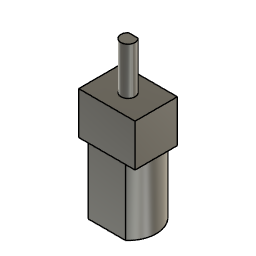
Whole Model (Autodesk Fusion 360 archive; units mm, degrees)
design "N20减速电机 v2"
Autodesk Fusion 360 part; units mm, degrees
(part 1 of 2)
sketch "草图2" plane through (0, 0, 0) normal (0, 0, 1) x (1, 0, 0)
  circle A0 centre (0, 0) radius 1.5
  line L0 (0, 1.12) -> (-0.9978, 1.12)
  line L1 (0, 1.12) -> (0.9978, 1.12)
  dimension "d8" = 3
  dimension "d9" = 1.12
  constraint coincident A0.centre origin
  constraint coincident A0 L0.end
  constraint coincident A0 L1.end
  measures "d8" diameter of A0
  measures "d9" distance of A0.centre L0.start
extrude "拉伸1" add sketch "草图2" along normal blind 10 contours A0 L0 L1 picked at (0.0212, -0.6237) makes body 1
extrude "拉伸2" add sketch "草图2" along normal blind 3 separate body contours A0 L0 L1 picked at (-0.0725, 1.368) makes body 2
sketch "草图4" plane through (0, 0, 0) normal (0, 0, 1) x (1, 0, 0)
  line L0 (-6, 0) -> (-6, -4.5)
  line L1 (-6, -4.5) -> (6, -4.5)
  line L2 (6, -4.5) -> (6, 4.5)
  line L3 (6, 4.5) -> (-6, 4.5)
  line L4 (-6, 4.5) -> (-6, 0)
  dimension "d14" = 6
  dimension "d15" = 4.5
  dimension "d16" = 12
  dimension "d17" = 9
  dimension "d18" = 12
  constraint perpendicular L0 L1
  constraint perpendicular L1 L2
  constraint perpendicular L2 L3
  measures "d14" distance of origin L0.start
  measures "d15" distance of L0.start L0.end
  measures "d16" distance of L0.end L1.end
  measures "d17" distance of L1.end L2.end
  measures "d18" distance of L2.end L3.end
extrude "拉伸3" add sketch "草图4" against normal blind 9 separate body makes body 3
sketch "草图6" plane through (0, 0, -9) normal (0, 0, -1) x (1, 0, 0)
  line L0 (-6, 4.5) -> (-6, -4.5)
  line L1 (-6, -4.5) -> (6, -4.5)
  line L2 (6, -4.5) -> (6, 4.5)
  line L3 (6, 4.5) -> (-6, 4.5)
  line L4 (0, -4.5) -> (0, -4.75)
  line L5 (0, -4.75) -> (3.6657, -4.75)
  line L6 (0, -4.75) -> (-3.6657, -4.75)
  line L7 (0, 4.5) -> (0, 4.75)
  line L8 (0, 4.75) -> (3.6657, 4.75)
  line L9 (0, 4.75) -> (-3.6657, 4.75)
  arc A0 (3.6657, -4.75) -> (3.6657, 4.75) centre (0, 0) ccw
  arc A1 (-3.6657, 4.75) -> (-3.6657, -4.75) centre (0, 0) ccw
  dimension "d21" = 12
  dimension "d22" = 4.75
  dimension "d23" = 4.75
  constraint coincident A0.centre A1.centre
  constraint perpendicular L1 L4
  constraint perpendicular L4 L5
  constraint perpendicular L4 L6
  constraint parallel L4 L7
  constraint perpendicular L7 L8
  constraint coincident L9.end A0
  constraint perpendicular L7 L9
  constraint coincident L1 L4.start
  constraint coincident L3 L7.start
  constraint concentric A0 A1
  measures "d21" diameter of A0
  measures "d22" distance of A0.centre L4.end
  measures "d23" distance of A0.centre L7.end
extrude "拉伸4" add sketch "草图6" along normal blind 14 separate body contours L1 L3 A0 A1 makes body 4
equation "d22 = ( 9.5 / 2 ) * 1 mm"

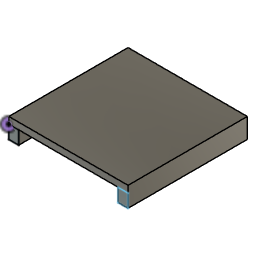
design "電機控製模塊"
Autodesk Fusion 360 part; units mm, degrees
sketch "草图1" plane through (0, 0, 0) normal (0, 0, 1) x (1, 0, 0)
  line L0 (0, 0) -> (18, 0)
  line L1 (18, 0) -> (18, 18)
  line L2 (18, 18) -> (0, 18)
  line L3 (0, 18) -> (0, 0)
  dimension "d1" = 18
  dimension "d2" = 18
  constraint horizontal L0
  constraint vertical L1
  constraint horizontal L2
  constraint vertical L3
  constraint coincident L0.start L3.end
  measures "d1" distance of L0.start L0.end
  measures "d2" distance of L0.start L2.end
extrude "拉伸1" add sketch "草图1" along normal blind 1
sketch "草图2" plane through (0, 0, 0) normal (0, 1, 0) x (1, 0, 0)
  line L0 (0, 0) -> (1.5, 0)
  line L1 (1.5, 0) -> (1.5, 2)
  line L2 (1.5, 2) -> (0, 2)
  line L3 (0, 2) -> (0, 0)
  line L4 (18, 0) -> (16.5, 0)
  line L5 (16.5, 0) -> (16.5, 2)
  line L6 (16.5, 2) -> (18, 2)
  line L7 (18, 2) -> (18, 0)
  dimension "d5" = 1.5
  dimension "d6" = 2
  dimension "d7" = 1.5
  dimension "d8" = 2
  constraint horizontal L0
  constraint vertical L1
  constraint horizontal L2
  constraint vertical L3
  constraint coincident L0.start L3.end
  constraint horizontal L4
  constraint vertical L5
  constraint horizontal L6
  constraint vertical L7
  measures "d5" distance of L0.start L0.end
  measures "d6" distance of L0.start L2.end
  measures "d7" distance of L4.start L4.end
  measures "d8" distance of L4.start L6.end
extrude "拉伸2" add sketch "草图2" along normal blind 18 contours L0 L1 L2 L3
extrude "拉伸3" add sketch "草图2" along normal blind 18 contours L4 L5 L6 L7

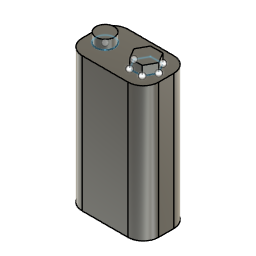
design "9V电池 v1"
Autodesk Fusion 360 part; units mm, degrees
sketch "草图1" plane through (0, 0, 0) normal (0, 0, 1) x (1, 0, 0)
  line L0 (-7.5, 7.5) -> (7.5, 7.5)
  line L1 (12.5, 2.5) -> (12.5, -2.5)
  line L2 (7.5, -7.5) -> (-7.5, -7.5)
  line L3 (-12.5, -2.5) -> (-12.5, 2.5)
  line L4 (-20, 0) -> (35, 0) construction
  line L5 (0, -15) -> (0, 25) construction
  arc A0 (-7.5, 7.5) -> (-12.5, 2.5) centre (-7.5, 2.5) ccw
  arc A1 (12.5, 2.5) -> (7.5, 7.5) centre (7.5, 2.5) ccw
  arc A2 (-12.5, -2.5) -> (-7.5, -7.5) centre (-7.5, -2.5) ccw
  arc A3 (7.5, -7.5) -> (12.5, -2.5) centre (7.5, -2.5) ccw
  point P0 (12.5, 7.5)
  point P1 (12.5, -7.5)
  point P2 (-12.5, -7.5)
  dimension "d1" = 25
  dimension "d2" = 15
  dimension "d3" = 5
  dimension "d4" = 5
  dimension "d5" = 5
  dimension "d6" = 5
  constraint horizontal L0
  constraint vertical L1
  constraint horizontal L2
  constraint vertical L3
  constraint horizontal L4
  constraint vertical L5
  constraint symmetric L1 L3 L5
  constraint symmetric L0 L2 L4
  constraint tangent L3 A0
  constraint tangent L0 A0
  constraint coincident P0 L0
  constraint coincident P0 L1
  constraint tangent L0 A1
  constraint tangent L1 A1
  constraint coincident P2 L3
  constraint coincident P2 L2
  constraint tangent L3 A2
  constraint tangent L2 A2
  constraint coincident P1 L2
  constraint coincident P1 L1
  constraint tangent L2 A3
  constraint tangent L1 A3
  measures "d1" distance of P1 P2
  measures "d2" distance of P0 P1
  measures "d3" radius of A0
  measures "d4" radius of A1
  measures "d5" radius of A2
  measures "d6" radius of A3
extrude "拉伸1" add sketch "草图1" against normal blind 44 makes body 1
sketch "草图3" plane through (0, 0, 0) normal (0, 0, 1) x (1, 0, 0)
  circle A0 centre (-7.5, 0) radius 3
  line L0 (3.9367, 3.4268) -> (2.0007, -0.0735)
  line L1 (4.064, -3.5003) -> (2.0007, -0.0735)
  line L2 (4.064, -3.5003) -> (8.0633, -3.4268)
  line L3 (8.0633, -3.4268) -> (9.9993, 0.0735)
  line L4 (9.9993, 0.0735) -> (7.936, 3.5003)
  line L5 (7.936, 3.5003) -> (3.9367, 3.4268)
  dimension "d9" = 6
  measures "d9" diameter of A0
extrude "拉伸2" add sketch "草图3" along normal blind 3 separate body contours A0 makes body 2
extrude "拉伸3" add sketch "草图3" along normal blind 3 separate body contours L0 L1 L2 L3 L4 L5 makes body 3

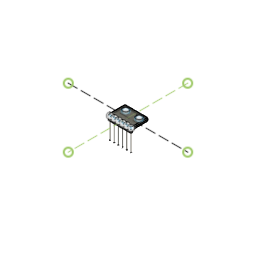
design "BMP280 v2"
Autodesk Fusion 360 part; units mm, degrees
sketch "草图1" plane through (0, 0, 0) normal (0, 0, 1) x (1, 0, 0)
  line L0 (-7.5, 5.5) -> (7.5, 5.5)
  line L1 (7.5, 5.5) -> (7.5, -5.5)
  line L2 (7.5, -5.5) -> (-7.5, -5.5)
  line L3 (-7.5, -5.5) -> (-7.5, 5.5)
  line L4 (0, 40) -> (0, -40) construction
  line L5 (-40, 0) -> (40, 0) construction
  circle A0 centre (-4.5, 3) radius 2
  circle A1 centre (4.5, 3) radius 2
  circle A2 centre (7, -5) radius 0.25
  circle A3 centre (4.2, -5) radius 0.25
  circle A4 centre (1.4, -5) radius 0.25
  circle A5 centre (-1.4, -5) radius 0.25
  circle A6 centre (-4.2, -5) radius 0.25
  circle A7 centre (-7, -5) radius 0.25
  line L6 (-7.5, -5.5) -> (7.5, -5.5)
  line L7 (7.5, -5.5) -> (7.5, -4.5)
  line L8 (7.5, -4.5) -> (-7.5, -4.5)
  line L9 (-7.5, -4.5) -> (-7.5, -5.5)
  dimension "d1" = 15
  dimension "d2" = 11
  dimension "d3" = 4
  dimension "d4" = 4
  dimension "d10" = 0.5
  dimension "d13" = -14
  dimension "d14" = 0
  constraint horizontal L0
  constraint vertical L1
  constraint horizontal L2
  constraint vertical L3
  constraint perpendicular L2 L4
  constraint perpendicular L3 L5
  constraint symmetric L0 L2 L5
  constraint symmetric L1 L3 L4
  constraint horizontal L6
  constraint vertical L7
  constraint horizontal L8
  constraint vertical L9
  constraint coincident L1 L7.end
  measures "d1" distance of L1.end L2.end
  measures "d2" distance of L0.end L1.end
  measures "d3" diameter of A0
  measures "d4" diameter of A1
  measures "d10" diameter of A2
extrude "拉伸1" add sketch "草图1" along normal mid plane 2 makes body 1
extrude "拉伸2" add sketch "草图1" along normal blind 2 separate body contours A7 makes body 2
extrude "拉伸3" add sketch "草图1" against normal blind 14 separate body contours A7 makes body 3
extrude "拉伸4" add sketch "草图1" along normal blind 2 separate body contours A6 makes body 4
extrude "拉伸5" add sketch "草图1" against normal blind 14 separate body contours A6 makes body 5
extrude "拉伸6" add sketch "草图1" along normal blind 2 separate body contours A5 makes body 6
extrude "拉伸7" add sketch "草图1" against normal blind 14 separate body contours A5 makes body 7
extrude "拉伸8" add sketch "草图1" along normal blind 2 separate body contours A4 makes body 8
extrude "拉伸9" add sketch "草图1" against normal blind 14 separate body contours A4 makes body 9
extrude "拉伸10" add sketch "草图1" along normal blind 2 separate body contours A3 makes body 10
extrude "拉伸11" add sketch "草图1" against normal blind 14 separate body contours A3 makes body 11
extrude "拉伸12" add sketch "草图1" along normal blind 2 separate body contours A2 makes body 12
extrude "拉伸13" add sketch "草图1" against normal blind 14 separate body contours A2 makes body 13
sketch "草图2" plane through (0, 0, -1) normal (0, 0, -1) x (1, 0, 0)
  circle A0 centre (4.5, -3) radius 2
  circle A1 centre (-4.5, -3) radius 2
  circle A2 centre (-1.4, 5) radius 0.25
  circle A3 centre (-7, 5) radius 0.25
  circle A4 centre (-4.2, 5) radius 0.25
  circle A5 centre (4.2, 5) radius 0.25
  circle A6 centre (7, 5) radius 0.25
  circle A7 centre (1.4, 5) radius 0.25
  line L0 (7.5, 5.5) -> (-7.5, 5.5)
  line L1 (-7.5, 5.5) -> (-7.5, -5.5)
  line L2 (-7.5, -5.5) -> (7.5, -5.5)
  line L3 (7.5, -5.5) -> (7.5, 5.5)
  line L4 (-7.5, 5.5) -> (7.5, 5.5)
  line L5 (7.5, 5.5) -> (7.5, 4.5)
  line L6 (7.5, 4.5) -> (-7.5, 4.5)
  line L7 (-7.5, 4.5) -> (-7.5, 5.5)
  constraint horizontal L4
  constraint vertical L5
  constraint horizontal L6
  constraint vertical L7
  constraint coincident L3 L5.end
  constraint coincident L0.end L1.start
extrude "拉伸14" add sketch "草图2" along normal blind 1.5 contours L0 L1 L3 L4 L5 L6 L7 bodies 1 3 5 7 9 11 13

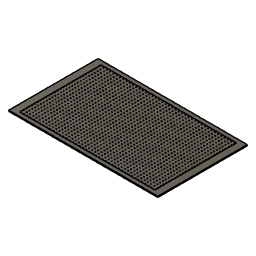
design "9_15万用板 v3"
Autodesk Fusion 360 part; units mm, degrees
sketch "草图1" plane through (0, 0, 0) normal (0, 0, 1) x (1, 0, 0)
  line L0 (-75, 45) -> (-75, -45)
  line L1 (-75, -45) -> (75, -45)
  line L2 (75, -45) -> (75, 45)
  line L3 (75, 45) -> (-75, 45)
  line L4 (0, 70) -> (0, -74.4256) construction
  line L5 (-80, 0) -> (100, 0) construction
  dimension "d1" = 90
  dimension "d2" = 150
  constraint vertical L0
  constraint perpendicular L0 L1
  constraint perpendicular L1 L2
  constraint perpendicular L0 L3
  constraint perpendicular L1 L4
  constraint perpendicular L0 L5
  constraint symmetric L1 L3 L5
  constraint symmetric L0 L2 L4
  measures "d1" distance of L0.start L0.end
  measures "d2" distance of L0.end L1.end
extrude "拉伸1" add sketch "草图1" along normal blind 1 makes body 1
sketch "草图2" plane through (0, 0, 0) normal (0, 0, 1) x (1, 0, 0)
  line L0 (-68, 41) -> (-68, -41)
  line L1 (-68, -41) -> (68, -41)
  line L2 (68, -41) -> (68, 41)
  line L3 (68, 41) -> (-68, 41)
  line L4 (0, 70) -> (0, -74.4256)
  line L5 (-80, 0) -> (100, 0)
  circle A0 centre (-67.5, -40.5) radius 0.5
  circle A1 centre (-64.2073, -40.5) radius 0.5
  circle A2 centre (-60.9146, -40.5) radius 0.5
  circle A3 centre (-57.622, -40.5) radius 0.5
  circle A4 centre (-54.3293, -40.5) radius 0.5
  circle A5 centre (-51.0366, -40.5) radius 0.5
  circle A6 centre (-47.7439, -40.5) radius 0.5
  circle A7 centre (-44.4512, -40.5) radius 0.5
  circle A8 centre (-41.1585, -40.5) radius 0.5
  circle A9 centre (-37.8659, -40.5) radius 0.5
  circle A10 centre (-34.5732, -40.5) radius 0.5
  circle A11 centre (-31.2805, -40.5) radius 0.5
  circle A12 centre (-27.9878, -40.5) radius 0.5
  circle A13 centre (-24.6951, -40.5) radius 0.5
  circle A14 centre (-21.4024, -40.5) radius 0.5
  circle A15 centre (-18.1098, -40.5) radius 0.5
  circle A16 centre (-14.8171, -40.5) radius 0.5
  circle A17 centre (-11.5244, -40.5) radius 0.5
  circle A18 centre (-8.2317, -40.5) radius 0.5
  circle A19 centre (-4.939, -40.5) radius 0.5
  circle A20 centre (-1.6463, -40.5) radius 0.5
  circle A21 centre (1.6463, -40.5) radius 0.5
  circle A22 centre (4.939, -40.5) radius 0.5
  circle A23 centre (8.2317, -40.5) radius 0.5
  circle A24 centre (11.5244, -40.5) radius 0.5
  circle A25 centre (14.8171, -40.5) radius 0.5
  circle A26 centre (18.1098, -40.5) radius 0.5
  circle A27 centre (21.4024, -40.5) radius 0.5
  circle A28 centre (24.6951, -40.5) radius 0.5
  circle A29 centre (27.9878, -40.5) radius 0.5
  circle A30 centre (31.2805, -40.5) radius 0.5
  circle A31 centre (34.5732, -40.5) radius 0.5
  circle A32 centre (37.8659, -40.5) radius 0.5
  circle A33 centre (41.1585, -40.5) radius 0.5
  circle A34 centre (44.4512, -40.5) radius 0.5
  circle A35 centre (47.7439, -40.5) radius 0.5
  circle A36 centre (51.0366, -40.5) radius 0.5
  circle A37 centre (54.3293, -40.5) radius 0.5
  circle A38 centre (57.622, -40.5) radius 0.5
  circle A39 centre (60.9146, -40.5) radius 0.5
  circle A40 centre (64.2073, -40.5) radius 0.5
  circle A41 centre (67.5, -40.5) radius 0.5
  circle A42 centre (-67.5, -37.6429) radius 0.5
  circle A43 centre (-64.2073, -37.6429) radius 0.5
  circle A44 centre (-60.9146, -37.6429) radius 0.5
  circle A45 centre (-57.622, -37.6429) radius 0.5
  circle A46 centre (-54.3293, -37.6429) radius 0.5
  circle A47 centre (-51.0366, -37.6429) radius 0.5
  circle A48 centre (-47.7439, -37.6429) radius 0.5
  circle A49 centre (-44.4512, -37.6429) radius 0.5
  circle A50 centre (-41.1585, -37.6429) radius 0.5
  circle A51 centre (-37.8659, -37.6429) radius 0.5
  circle A52 centre (-34.5732, -37.6429) radius 0.5
  circle A53 centre (-31.2805, -37.6429) radius 0.5
  circle A54 centre (-27.9878, -37.6429) radius 0.5
  circle A55 centre (-24.6951, -37.6429) radius 0.5
  circle A56 centre (-21.4024, -37.6429) radius 0.5
  circle A57 centre (-18.1098, -37.6429) radius 0.5
  circle A58 centre (-14.8171, -37.6429) radius 0.5
  circle A59 centre (-11.5244, -37.6429) radius 0.5
  circle A60 centre (-8.2317, -37.6429) radius 0.5
  circle A61 centre (-4.939, -37.6429) radius 0.5
  circle A62 centre (-1.6463, -37.6429) radius 0.5
  circle A63 centre (1.6463, -37.6429) radius 0.5
  circle A64 centre (4.939, -37.6429) radius 0.5
  circle A65 centre (8.2317, -37.6429) radius 0.5
  circle A66 centre (11.5244, -37.6429) radius 0.5
  circle A67 centre (14.8171, -37.6429) radius 0.5
  circle A68 centre (18.1098, -37.6429) radius 0.5
  circle A69 centre (21.4024, -37.6429) radius 0.5
  circle A70 centre (24.6951, -37.6429) radius 0.5
  circle A71 centre (27.9878, -37.6429) radius 0.5
  circle A72 centre (31.2805, -37.6429) radius 0.5
  circle A73 centre (34.5732, -37.6429) radius 0.5
  circle A74 centre (37.8659, -37.6429) radius 0.5
  circle A75 centre (41.1585, -37.6429) radius 0.5
  circle A76 centre (44.4512, -37.6429) radius 0.5
  circle A77 centre (47.7439, -37.6429) radius 0.5
  circle A78 centre (51.0366, -37.6429) radius 0.5
  circle A79 centre (54.3293, -37.6429) radius 0.5
  circle A80 centre (57.622, -37.6429) radius 0.5
  circle A81 centre (60.9146, -37.6429) radius 0.5
  circle A82 centre (64.2073, -37.6429) radius 0.5
  circle A83 centre (67.5, -37.6429) radius 0.5
  circle A84 centre (-67.5, -34.7857) radius 0.5
  circle A85 centre (-64.2073, -34.7857) radius 0.5
  circle A86 centre (-60.9146, -34.7857) radius 0.5
  circle A87 centre (-57.622, -34.7857) radius 0.5
  circle A88 centre (-54.3293, -34.7857) radius 0.5
  circle A89 centre (-51.0366, -34.7857) radius 0.5
  circle A90 centre (-47.7439, -34.7857) radius 0.5
  circle A91 centre (-44.4512, -34.7857) radius 0.5
  circle A92 centre (-41.1585, -34.7857) radius 0.5
  circle A93 centre (-37.8659, -34.7857) radius 0.5
  circle A94 centre (-34.5732, -34.7857) radius 0.5
  circle A95 centre (-31.2805, -34.7857) radius 0.5
  circle A96 centre (-27.9878, -34.7857) radius 0.5
  circle A97 centre (-24.6951, -34.7857) radius 0.5
  circle A98 centre (-21.4024, -34.7857) radius 0.5
  circle A99 centre (-18.1098, -34.7857) radius 0.5
  circle A100 centre (-14.8171, -34.7857) radius 0.5
  circle A101 centre (-11.5244, -34.7857) radius 0.5
  circle A102 centre (-8.2317, -34.7857) radius 0.5
  circle A103 centre (-4.939, -34.7857) radius 0.5
  circle A104 centre (-1.6463, -34.7857) radius 0.5
  circle A105 centre (1.6463, -34.7857) radius 0.5
  circle A106 centre (4.939, -34.7857) radius 0.5
  circle A107 centre (8.2317, -34.7857) radius 0.5
  circle A108 centre (11.5244, -34.7857) radius 0.5
  circle A109 centre (14.8171, -34.7857) radius 0.5
  circle A110 centre (18.1098, -34.7857) radius 0.5
  circle A111 centre (21.4024, -34.7857) radius 0.5
  circle A112 centre (24.6951, -34.7857) radius 0.5
  circle A113 centre (27.9878, -34.7857) radius 0.5
  circle A114 centre (31.2805, -34.7857) radius 0.5
  circle A115 centre (34.5732, -34.7857) radius 0.5
  circle A116 centre (37.8659, -34.7857) radius 0.5
  circle A117 centre (41.1585, -34.7857) radius 0.5
  circle A118 centre (44.4512, -34.7857) radius 0.5
  circle A119 centre (47.7439, -34.7857) radius 0.5
  circle A120 centre (51.0366, -34.7857) radius 0.5
  circle A121 centre (54.3293, -34.7857) radius 0.5
  circle A122 centre (57.622, -34.7857) radius 0.5
  circle A123 centre (60.9146, -34.7857) radius 0.5
  circle A124 centre (64.2073, -34.7857) radius 0.5
  circle A125 centre (67.5, -34.7857) radius 0.5
  circle A126 centre (-67.5, -31.9286) radius 0.5
  circle A127 centre (-64.2073, -31.9286) radius 0.5
  circle A128 centre (-60.9146, -31.9286) radius 0.5
  circle A129 centre (-57.622, -31.9286) radius 0.5
  circle A130 centre (-54.3293, -31.9286) radius 0.5
  circle A131 centre (-51.0366, -31.9286) radius 0.5
  circle A132 centre (-47.7439, -31.9286) radius 0.5
  circle A133 centre (-44.4512, -31.9286) radius 0.5
  circle A134 centre (-41.1585, -31.9286) radius 0.5
  circle A135 centre (-37.8659, -31.9286) radius 0.5
  circle A136 centre (-34.5732, -31.9286) radius 0.5
  circle A137 centre (-31.2805, -31.9286) radius 0.5
  circle A138 centre (-27.9878, -31.9286) radius 0.5
  circle A139 centre (-24.6951, -31.9286) radius 0.5
  circle A140 centre (-21.4024, -31.9286) radius 0.5
  circle A141 centre (-18.1098, -31.9286) radius 0.5
  circle A142 centre (-14.8171, -31.9286) radius 0.5
  circle A143 centre (-11.5244, -31.9286) radius 0.5
  circle A144 centre (-8.2317, -31.9286) radius 0.5
  circle A145 centre (-4.939, -31.9286) radius 0.5
  circle A146 centre (-1.6463, -31.9286) radius 0.5
  circle A147 centre (1.6463, -31.9286) radius 0.5
  circle A148 centre (4.939, -31.9286) radius 0.5
  circle A149 centre (8.2317, -31.9286) radius 0.5
  circle A150 centre (11.5244, -31.9286) radius 0.5
  circle A151 centre (14.8171, -31.9286) radius 0.5
  circle A152 centre (18.1098, -31.9286) radius 0.5
  circle A153 centre (21.4024, -31.9286) radius 0.5
  circle A154 centre (24.6951, -31.9286) radius 0.5
  circle A155 centre (27.9878, -31.9286) radius 0.5
  circle A156 centre (31.2805, -31.9286) radius 0.5
  circle A157 centre (34.5732, -31.9286) radius 0.5
  circle A158 centre (37.8659, -31.9286) radius 0.5
  circle A159 centre (41.1585, -31.9286) radius 0.5
  circle A160 centre (44.4512, -31.9286) radius 0.5
  circle A161 centre (47.7439, -31.9286) radius 0.5
  circle A162 centre (51.0366, -31.9286) radius 0.5
  circle A163 centre (54.3293, -31.9286) radius 0.5
  circle A164 centre (57.622, -31.9286) radius 0.5
  circle A165 centre (60.9146, -31.9286) radius 0.5
  circle A166 centre (64.2073, -31.9286) radius 0.5
  circle A167 centre (67.5, -31.9286) radius 0.5
  circle A168 centre (-67.5, -29.0714) radius 0.5
  circle A169 centre (-64.2073, -29.0714) radius 0.5
  circle A170 centre (-60.9146, -29.0714) radius 0.5
  circle A171 centre (-57.622, -29.0714) radius 0.5
  circle A172 centre (-54.3293, -29.0714) radius 0.5
  circle A173 centre (-51.0366, -29.0714) radius 0.5
  circle A174 centre (-47.7439, -29.0714) radius 0.5
  circle A175 centre (-44.4512, -29.0714) radius 0.5
  circle A176 centre (-41.1585, -29.0714) radius 0.5
  circle A177 centre (-37.8659, -29.0714) radius 0.5
  circle A178 centre (-34.5732, -29.0714) radius 0.5
  circle A179 centre (-31.2805, -29.0714) radius 0.5
  circle A180 centre (-27.9878, -29.0714) radius 0.5
  circle A181 centre (-24.6951, -29.0714) radius 0.5
  circle A182 centre (-21.4024, -29.0714) radius 0.5
  circle A183 centre (-18.1098, -29.0714) radius 0.5
  circle A184 centre (-14.8171, -29.0714) radius 0.5
  circle A185 centre (-11.5244, -29.0714) radius 0.5
  circle A186 centre (-8.2317, -29.0714) radius 0.5
  circle A187 centre (-4.939, -29.0714) radius 0.5
  circle A188 centre (-1.6463, -29.0714) radius 0.5
  circle A189 centre (1.6463, -29.0714) radius 0.5
  circle A190 centre (4.939, -29.0714) radius 0.5
  circle A191 centre (8.2317, -29.0714) radius 0.5
  circle A192 centre (11.5244, -29.0714) radius 0.5
  circle A193 centre (14.8171, -29.0714) radius 0.5
  circle A194 centre (18.1098, -29.0714) radius 0.5
  circle A195 centre (21.4024, -29.0714) radius 0.5
  circle A196 centre (24.6951, -29.0714) radius 0.5
  circle A197 centre (27.9878, -29.0714) radius 0.5
  circle A198 centre (31.2805, -29.0714) radius 0.5
  circle A199 centre (34.5732, -29.0714) radius 0.5
  circle A200 centre (37.8659, -29.0714) radius 0.5
  circle A201 centre (41.1585, -29.0714) radius 0.5
  circle A202 centre (44.4512, -29.0714) radius 0.5
  circle A203 centre (47.7439, -29.0714) radius 0.5
  circle A204 centre (51.0366, -29.0714) radius 0.5
  circle A205 centre (54.3293, -29.0714) radius 0.5
  circle A206 centre (57.622, -29.0714) radius 0.5
  circle A207 centre (60.9146, -29.0714) radius 0.5
  circle A208 centre (64.2073, -29.0714) radius 0.5
  circle A209 centre (67.5, -29.0714) radius 0.5
  circle A210 centre (-67.5, -26.2143) radius 0.5
  circle A211 centre (-64.2073, -26.2143) radius 0.5
  circle A212 centre (-60.9146, -26.2143) radius 0.5
  circle A213 centre (-57.622, -26.2143) radius 0.5
  circle A214 centre (-54.3293, -26.2143) radius 0.5
  circle A215 centre (-51.0366, -26.2143) radius 0.5
  circle A216 centre (-47.7439, -26.2143) radius 0.5
  circle A217 centre (-44.4512, -26.2143) radius 0.5
  circle A218 centre (-41.1585, -26.2143) radius 0.5
  circle A219 centre (-37.8659, -26.2143) radius 0.5
  circle A220 centre (-34.5732, -26.2143) radius 0.5
  circle A221 centre (-31.2805, -26.2143) radius 0.5
  circle A222 centre (-27.9878, -26.2143) radius 0.5
  circle A223 centre (-24.6951, -26.2143) radius 0.5
  circle A224 centre (-21.4024, -26.2143) radius 0.5
  circle A225 centre (-18.1098, -26.2143) radius 0.5
  circle A226 centre (-14.8171, -26.2143) radius 0.5
  circle A227 centre (-11.5244, -26.2143) radius 0.5
  circle A228 centre (-8.2317, -26.2143) radius 0.5
  circle A229 centre (-4.939, -26.2143) radius 0.5
  circle A230 centre (-1.6463, -26.2143) radius 0.5
  circle A231 centre (1.6463, -26.2143) radius 0.5
  circle A232 centre (4.939, -26.2143) radius 0.5
  circle A233 centre (8.2317, -26.2143) radius 0.5
  circle A234 centre (11.5244, -26.2143) radius 0.5
  circle A235 centre (14.8171, -26.2143) radius 0.5
  circle A236 centre (18.1098, -26.2143) radius 0.5
  circle A237 centre (21.4024, -26.2143) radius 0.5
  circle A238 centre (24.6951, -26.2143) radius 0.5
  circle A239 centre (27.9878, -26.2143) radius 0.5
  circle A240 centre (31.2805, -26.2143) radius 0.5
  circle A241 centre (34.5732, -26.2143) radius 0.5
  circle A242 centre (37.8659, -26.2143) radius 0.5
  circle A243 centre (41.1585, -26.2143) radius 0.5
  circle A244 centre (44.4512, -26.2143) radius 0.5
  circle A245 centre (47.7439, -26.2143) radius 0.5
  circle A246 centre (51.0366, -26.2143) radius 0.5
  circle A247 centre (54.3293, -26.2143) radius 0.5
  circle A248 centre (57.622, -26.2143) radius 0.5
  circle A249 centre (60.9146, -26.2143) radius 0.5
  circle A250 centre (64.2073, -26.2143) radius 0.5
  circle A251 centre (67.5, -26.2143) radius 0.5
  circle A252 centre (-67.5, -23.3571) radius 0.5
  circle A253 centre (-64.2073, -23.3571) radius 0.5
  circle A254 centre (-60.9146, -23.3571) radius 0.5
  circle A255 centre (-57.622, -23.3571) radius 0.5
  circle A256 centre (-54.3293, -23.3571) radius 0.5
  circle A257 centre (-51.0366, -23.3571) radius 0.5
  circle A258 centre (-47.7439, -23.3571) radius 0.5
  circle A259 centre (-44.4512, -23.3571) radius 0.5
  circle A260 centre (-41.1585, -23.3571) radius 0.5
  circle A261 centre (-37.8659, -23.3571) radius 0.5
  circle A262 centre (-34.5732, -23.3571) radius 0.5
  circle A263 centre (-31.2805, -23.3571) radius 0.5
  circle A264 centre (-27.9878, -23.3571) radius 0.5
  circle A265 centre (-24.6951, -23.3571) radius 0.5
  circle A266 centre (-21.4024, -23.3571) radius 0.5
  circle A267 centre (-18.1098, -23.3571) radius 0.5
  circle A268 centre (-14.8171, -23.3571) radius 0.5
  circle A269 centre (-11.5244, -23.3571) radius 0.5
  circle A270 centre (-8.2317, -23.3571) radius 0.5
  circle A271 centre (-4.939, -23.3571) radius 0.5
  circle A272 centre (-1.6463, -23.3571) radius 0.5
  circle A273 centre (1.6463, -23.3571) radius 0.5
  circle A274 centre (4.939, -23.3571) radius 0.5
  circle A275 centre (8.2317, -23.3571) radius 0.5
  circle A276 centre (11.5244, -23.3571) radius 0.5
  circle A277 centre (14.8171, -23.3571) radius 0.5
  circle A278 centre (18.1098, -23.3571) radius 0.5
  circle A279 centre (21.4024, -23.3571) radius 0.5
  circle A280 centre (24.6951, -23.3571) radius 0.5
  circle A281 centre (27.9878, -23.3571) radius 0.5
  circle A282 centre (31.2805, -23.3571) radius 0.5
  circle A283 centre (34.5732, -23.3571) radius 0.5
  circle A284 centre (37.8659, -23.3571) radius 0.5
  circle A285 centre (41.1585, -23.3571) radius 0.5
  circle A286 centre (44.4512, -23.3571) radius 0.5
  circle A287 centre (47.7439, -23.3571) radius 0.5
  circle A288 centre (51.0366, -23.3571) radius 0.5
  circle A289 centre (54.3293, -23.3571) radius 0.5
  circle A290 centre (57.622, -23.3571) radius 0.5
  circle A291 centre (60.9146, -23.3571) radius 0.5
  circle A292 centre (64.2073, -23.3571) radius 0.5
  circle A293 centre (67.5, -23.3571) radius 0.5
  circle A294 centre (-67.5, -20.5) radius 0.5
  circle A295 centre (-64.2073, -20.5) radius 0.5
  circle A296 centre (-60.9146, -20.5) radius 0.5
  circle A297 centre (-57.622, -20.5) radius 0.5
  circle A298 centre (-54.3293, -20.5) radius 0.5
  circle A299 centre (-51.0366, -20.5) radius 0.5
  circle A300 centre (-47.7439, -20.5) radius 0.5
  circle A301 centre (-44.4512, -20.5) radius 0.5
  circle A302 centre (-41.1585, -20.5) radius 0.5
  circle A303 centre (-37.8659, -20.5) radius 0.5
  circle A304 centre (-34.5732, -20.5) radius 0.5
  circle A305 centre (-31.2805, -20.5) radius 0.5
  circle A306 centre (-27.9878, -20.5) radius 0.5
  circle A307 centre (-24.6951, -20.5) radius 0.5
  circle A308 centre (-21.4024, -20.5) radius 0.5
  circle A309 centre (-18.1098, -20.5) radius 0.5
  circle A310 centre (-14.8171, -20.5) radius 0.5
  circle A311 centre (-11.5244, -20.5) radius 0.5
  circle A312 centre (-8.2317, -20.5) radius 0.5
  circle A313 centre (-4.939, -20.5) radius 0.5
  circle A314 centre (-1.6463, -20.5) radius 0.5
  circle A315 centre (1.6463, -20.5) radius 0.5
  circle A316 centre (4.939, -20.5) radius 0.5
  circle A317 centre (8.2317, -20.5) radius 0.5
  circle A318 centre (11.5244, -20.5) radius 0.5
  circle A319 centre (14.8171, -20.5) radius 0.5
  circle A320 centre (18.1098, -20.5) radius 0.5
  circle A321 centre (21.4024, -20.5) radius 0.5
  circle A322 centre (24.6951, -20.5) radius 0.5
  circle A323 centre (27.9878, -20.5) radius 0.5
  circle A324 centre (31.2805, -20.5) radius 0.5
  circle A325 centre (34.5732, -20.5) radius 0.5
  circle A326 centre (37.8659, -20.5) radius 0.5
  circle A327 centre (41.1585, -20.5) radius 0.5
  circle A328 centre (44.4512, -20.5) radius 0.5
  circle A329 centre (47.7439, -20.5) radius 0.5
  circle A330 centre (51.0366, -20.5) radius 0.5
  circle A331 centre (54.3293, -20.5) radius 0.5
  circle A332 centre (57.622, -20.5) radius 0.5
  circle A333 centre (60.9146, -20.5) radius 0.5
  circle A334 centre (64.2073, -20.5) radius 0.5
  circle A335 centre (67.5, -20.5) radius 0.5
  circle A336 centre (-67.5, -17.6429) radius 0.5
  circle A337 centre (-64.2073, -17.6429) radius 0.5
  circle A338 centre (-60.9146, -17.6429) radius 0.5
  circle A339 centre (-57.622, -17.6429) radius 0.5
  circle A340 centre (-54.3293, -17.6429) radius 0.5
  circle A341 centre (-51.0366, -17.6429) radius 0.5
  circle A342 centre (-47.7439, -17.6429) radius 0.5
  circle A343 centre (-44.4512, -17.6429) radius 0.5
  circle A344 centre (-41.1585, -17.6429) radius 0.5
  circle A345 centre (-37.8659, -17.6429) radius 0.5
  circle A346 centre (-34.5732, -17.6429) radius 0.5
  circle A347 centre (-31.2805, -17.6429) radius 0.5
  circle A348 centre (-27.9878, -17.6429) radius 0.5
  circle A349 centre (-24.6951, -17.6429) radius 0.5
  circle A350 centre (-21.4024, -17.6429) radius 0.5
  circle A351 centre (-18.1098, -17.6429) radius 0.5
  circle A352 centre (-14.8171, -17.6429) radius 0.5
  circle A353 centre (-11.5244, -17.6429) radius 0.5
  circle A354 centre (-8.2317, -17.6429) radius 0.5
  circle A355 centre (-4.939, -17.6429) radius 0.5
  circle A356 centre (-1.6463, -17.6429) radius 0.5
  circle A357 centre (1.6463, -17.6429) radius 0.5
  circle A358 centre (4.939, -17.6429) radius 0.5
  circle A359 centre (8.2317, -17.6429) radius 0.5
  circle A360 centre (11.5244, -17.6429) radius 0.5
  circle A361 centre (14.8171, -17.6429) radius 0.5
  circle A362 centre (18.1098, -17.6429) radius 0.5
  circle A363 centre (21.4024, -17.6429) radius 0.5
  circle A364 centre (24.6951, -17.6429) radius 0.5
  circle A365 centre (27.9878, -17.6429) radius 0.5
  circle A366 centre (31.2805, -17.6429) radius 0.5
  circle A367 centre (34.5732, -17.6429) radius 0.5
  circle A368 centre (37.8659, -17.6429) radius 0.5
  circle A369 centre (41.1585, -17.6429) radius 0.5
  circle A370 centre (44.4512, -17.6429) radius 0.5
  circle A371 centre (47.7439, -17.6429) radius 0.5
  circle A372 centre (51.0366, -17.6429) radius 0.5
  circle A373 centre (54.3293, -17.6429) radius 0.5
  circle A374 centre (57.622, -17.6429) radius 0.5
  circle A375 centre (60.9146, -17.6429) radius 0.5
  circle A376 centre (64.2073, -17.6429) radius 0.5
  circle A377 centre (67.5, -17.6429) radius 0.5
  circle A378 centre (-67.5, -14.7857) radius 0.5
  circle A379 centre (-64.2073, -14.7857) radius 0.5
  circle A380 centre (-60.9146, -14.7857) radius 0.5
  circle A381 centre (-57.622, -14.7857) radius 0.5
  circle A382 centre (-54.3293, -14.7857) radius 0.5
  circle A383 centre (-51.0366, -14.7857) radius 0.5
  circle A384 centre (-47.7439, -14.7857) radius 0.5
  circle A385 centre (-44.4512, -14.7857) radius 0.5
  circle A386 centre (-41.1585, -14.7857) radius 0.5
  circle A387 centre (-37.8659, -14.7857) radius 0.5
  circle A388 centre (-34.5732, -14.7857) radius 0.5
  circle A389 centre (-31.2805, -14.7857) radius 0.5
  circle A390 centre (-27.9878, -14.7857) radius 0.5
  circle A391 centre (-24.6951, -14.7857) radius 0.5
  circle A392 centre (-21.4024, -14.7857) radius 0.5
  circle A393 centre (-18.1098, -14.7857) radius 0.5
  circle A394 centre (-14.8171, -14.7857) radius 0.5
  circle A395 centre (-11.5244, -14.7857) radius 0.5
  circle A396 centre (-8.2317, -14.7857) radius 0.5
  circle A397 centre (-4.939, -14.7857) radius 0.5
  circle A398 centre (-1.6463, -14.7857) radius 0.5
  circle A399 centre (1.6463, -14.7857) radius 0.5
  circle A400 centre (4.939, -14.7857) radius 0.5
  circle A401 centre (8.2317, -14.7857) radius 0.5
  circle A402 centre (11.5244, -14.7857) radius 0.5
  circle A403 centre (14.8171, -14.7857) radius 0.5
  circle A404 centre (18.1098, -14.7857) radius 0.5
  circle A405 centre (21.4024, -14.7857) radius 0.5
  circle A406 centre (24.6951, -14.7857) radius 0.5
  circle A407 centre (27.9878, -14.7857) radius 0.5
  circle A408 centre (31.2805, -14.7857) radius 0.5
  circle A409 centre (34.5732, -14.7857) radius 0.5
  circle A410 centre (37.8659, -14.7857) radius 0.5
  circle A411 centre (41.1585, -14.7857) radius 0.5
  circle A412 centre (44.4512, -14.7857) radius 0.5
  circle A413 centre (47.7439, -14.7857) radius 0.5
  circle A414 centre (51.0366, -14.7857) radius 0.5
  circle A415 centre (54.3293, -14.7857) radius 0.5
  circle A416 centre (57.622, -14.7857) radius 0.5
  circle A417 centre (60.9146, -14.7857) radius 0.5
  circle A418 centre (64.2073, -14.7857) radius 0.5
  circle A419 centre (67.5, -14.7857) radius 0.5
  circle A420 centre (-67.5, -11.9286) radius 0.5
  circle A421 centre (-64.2073, -11.9286) radius 0.5
  circle A422 centre (-60.9146, -11.9286) radius 0.5
  circle A423 centre (-57.622, -11.9286) radius 0.5
  circle A424 centre (-54.3293, -11.9286) radius 0.5
  circle A425 centre (-51.0366, -11.9286) radius 0.5
  circle A426 centre (-47.7439, -11.9286) radius 0.5
  circle A427 centre (-44.4512, -11.9286) radius 0.5
  circle A428 centre (-41.1585, -11.9286) radius 0.5
  circle A429 centre (-37.8659, -11.9286) radius 0.5
  circle A430 centre (-34.5732, -11.9286) radius 0.5
  circle A431 centre (-31.2805, -11.9286) radius 0.5
  circle A432 centre (-27.9878, -11.9286) radius 0.5
  circle A433 centre (-24.6951, -11.9286) radius 0.5
  circle A434 centre (-21.4024, -11.9286) radius 0.5
  circle A435 centre (-18.1098, -11.9286) radius 0.5
  circle A436 centre (-14.8171, -11.9286) radius 0.5
  circle A437 centre (-11.5244, -11.9286) radius 0.5
  circle A438 centre (-8.2317, -11.9286) radius 0.5
  circle A439 centre (-4.939, -11.9286) radius 0.5
  circle A440 centre (-1.6463, -11.9286) radius 0.5
  circle A441 centre (1.6463, -11.9286) radius 0.5
  circle A442 centre (4.939, -11.9286) radius 0.5
  circle A443 centre (8.2317, -11.9286) radius 0.5
  circle A444 centre (11.5244, -11.9286) radius 0.5
  circle A445 centre (14.8171, -11.9286) radius 0.5
  circle A446 centre (18.1098, -11.9286) radius 0.5
  circle A447 centre (21.4024, -11.9286) radius 0.5
  circle A448 centre (24.6951, -11.9286) radius 0.5
  circle A449 centre (27.9878, -11.9286) radius 0.5
  circle A450 centre (31.2805, -11.9286) radius 0.5
  circle A451 centre (34.5732, -11.9286) radius 0.5
  circle A452 centre (37.8659, -11.9286) radius 0.5
  circle A453 centre (41.1585, -11.9286) radius 0.5
  circle A454 centre (44.4512, -11.9286) radius 0.5
  circle A455 centre (47.7439, -11.9286) radius 0.5
  circle A456 centre (51.0366, -11.9286) radius 0.5
  circle A457 centre (54.3293, -11.9286) radius 0.5
  circle A458 centre (57.622, -11.9286) radius 0.5
  circle A459 centre (60.9146, -11.9286) radius 0.5
  circle A460 centre (64.2073, -11.9286) radius 0.5
  circle A461 centre (67.5, -11.9286) radius 0.5
  circle A462 centre (-67.5, -9.0714) radius 0.5
  circle A463 centre (-64.2073, -9.0714) radius 0.5
  circle A464 centre (-60.9146, -9.0714) radius 0.5
  circle A465 centre (-57.622, -9.0714) radius 0.5
  circle A466 centre (-54.3293, -9.0714) radius 0.5
  circle A467 centre (-51.0366, -9.0714) radius 0.5
  circle A468 centre (-47.7439, -9.0714) radius 0.5
  circle A469 centre (-44.4512, -9.0714) radius 0.5
  circle A470 centre (-41.1585, -9.0714) radius 0.5
  circle A471 centre (-37.8659, -9.0714) radius 0.5
  circle A472 centre (-34.5732, -9.0714) radius 0.5
  circle A473 centre (-31.2805, -9.0714) radius 0.5
  circle A474 centre (-27.9878, -9.0714) radius 0.5
  circle A475 centre (-24.6951, -9.0714) radius 0.5
  circle A476 centre (-21.4024, -9.0714) radius 0.5
  circle A477 centre (-18.1098, -9.0714) radius 0.5
  circle A478 centre (-14.8171, -9.0714) radius 0.5
  circle A479 centre (-11.5244, -9.0714) radius 0.5
  circle A480 centre (-8.2317, -9.0714) radius 0.5
  circle A481 centre (-4.939, -9.0714) radius 0.5
  circle A482 centre (-1.6463, -9.0714) radius 0.5
  circle A483 centre (1.6463, -9.0714) radius 0.5
  circle A484 centre (4.939, -9.0714) radius 0.5
  circle A485 centre (8.2317, -9.0714) radius 0.5
  circle A486 centre (11.5244, -9.0714) radius 0.5
  circle A487 centre (14.8171, -9.0714) radius 0.5
  circle A488 centre (18.1098, -9.0714) radius 0.5
  circle A489 centre (21.4024, -9.0714) radius 0.5
  circle A490 centre (24.6951, -9.0714) radius 0.5
  circle A491 centre (27.9878, -9.0714) radius 0.5
  circle A492 centre (31.2805, -9.0714) radius 0.5
  circle A493 centre (34.5732, -9.0714) radius 0.5
  circle A494 centre (37.8659, -9.0714) radius 0.5
  circle A495 centre (41.1585, -9.0714) radius 0.5
  circle A496 centre (44.4512, -9.0714) radius 0.5
  circle A497 centre (47.7439, -9.0714) radius 0.5
  circle A498 centre (51.0366, -9.0714) radius 0.5
  circle A499 centre (54.3293, -9.0714) radius 0.5
  circle A500 centre (57.622, -9.0714) radius 0.5
  circle A501 centre (60.9146, -9.0714) radius 0.5
  circle A502 centre (64.2073, -9.0714) radius 0.5
  circle A503 centre (67.5, -9.0714) radius 0.5
  circle A504 centre (-67.5, -6.2143) radius 0.5
  circle A505 centre (-64.2073, -6.2143) radius 0.5
  circle A506 centre (-60.9146, -6.2143) radius 0.5
  circle A507 centre (-57.622, -6.2143) radius 0.5
  circle A508 centre (-54.3293, -6.2143) radius 0.5
  circle A509 centre (-51.0366, -6.2143) radius 0.5
  circle A510 centre (-47.7439, -6.2143) radius 0.5
  circle A511 centre (-44.4512, -6.2143) radius 0.5
  circle A512 centre (-41.1585, -6.2143) radius 0.5
  circle A513 centre (-37.8659, -6.2143) radius 0.5
  circle A514 centre (-34.5732, -6.2143) radius 0.5
  circle A515 centre (-31.2805, -6.2143) radius 0.5
  circle A516 centre (-27.9878, -6.2143) radius 0.5
  circle A517 centre (-24.6951, -6.2143) radius 0.5
  circle A518 centre (-21.4024, -6.2143) radius 0.5
  circle A519 centre (-18.1098, -6.2143) radius 0.5
  circle A520 centre (-14.8171, -6.2143) radius 0.5
  circle A521 centre (-11.5244, -6.2143) radius 0.5
  circle A522 centre (-8.2317, -6.2143) radius 0.5
  circle A523 centre (-4.939, -6.2143) radius 0.5
  circle A524 centre (-1.6463, -6.2143) radius 0.5
  circle A525 centre (1.6463, -6.2143) radius 0.5
  circle A526 centre (4.939, -6.2143) radius 0.5
  circle A527 centre (8.2317, -6.2143) radius 0.5
  circle A528 centre (11.5244, -6.2143) radius 0.5
  circle A529 centre (14.8171, -6.2143) radius 0.5
  circle A530 centre (18.1098, -6.2143) radius 0.5
  circle A531 centre (21.4024, -6.2143) radius 0.5
  circle A532 centre (24.6951, -6.2143) radius 0.5
  circle A533 centre (27.9878, -6.2143) radius 0.5
  circle A534 centre (31.2805, -6.2143) radius 0.5
  circle A535 centre (34.5732, -6.2143) radius 0.5
  circle A536 centre (37.8659, -6.2143) radius 0.5
  circle A537 centre (41.1585, -6.2143) radius 0.5
  circle A538 centre (44.4512, -6.2143) radius 0.5
  circle A539 centre (47.7439, -6.2143) radius 0.5
  circle A540 centre (51.0366, -6.2143) radius 0.5
  circle A541 centre (54.3293, -6.2143) radius 0.5
  circle A542 centre (57.622, -6.2143) radius 0.5
  circle A543 centre (60.9146, -6.2143) radius 0.5
  circle A544 centre (64.2073, -6.2143) radius 0.5
  circle A545 centre (67.5, -6.2143) radius 0.5
  circle A546 centre (-67.5, -3.3571) radius 0.5
  circle A547 centre (-64.2073, -3.3571) radius 0.5
  circle A548 centre (-60.9146, -3.3571) radius 0.5
  circle A549 centre (-57.622, -3.3571) radius 0.5
  circle A550 centre (-54.3293, -3.3571) radius 0.5
  circle A551 centre (-51.0366, -3.3571) radius 0.5
  circle A552 centre (-47.7439, -3.3571) radius 0.5
  circle A553 centre (-44.4512, -3.3571) radius 0.5
  circle A554 centre (-41.1585, -3.3571) radius 0.5
  circle A555 centre (-37.8659, -3.3571) radius 0.5
  circle A556 centre (-34.5732, -3.3571) radius 0.5
  circle A557 centre (-31.2805, -3.3571) radius 0.5
  circle A558 centre (-27.9878, -3.3571) radius 0.5
  circle A559 centre (-24.6951, -3.3571) radius 0.5
  circle A560 centre (-21.4024, -3.3571) radius 0.5
  circle A561 centre (-18.1098, -3.3571) radius 0.5
  circle A562 centre (-14.8171, -3.3571) radius 0.5
  circle A563 centre (-11.5244, -3.3571) radius 0.5
  circle A564 centre (-8.2317, -3.3571) radius 0.5
  circle A565 centre (-4.939, -3.3571) radius 0.5
  circle A566 centre (-1.6463, -3.3571) radius 0.5
  circle A567 centre (1.6463, -3.3571) radius 0.5
  circle A568 centre (4.939, -3.3571) radius 0.5
  circle A569 centre (8.2317, -3.3571) radius 0.5
  circle A570 centre (11.5244, -3.3571) radius 0.5
  circle A571 centre (14.8171, -3.3571) radius 0.5
  circle A572 centre (18.1098, -3.3571) radius 0.5
  circle A573 centre (21.4024, -3.3571) radius 0.5
  circle A574 centre (24.6951, -3.3571) radius 0.5
  circle A575 centre (27.9878, -3.3571) radius 0.5
  circle A576 centre (31.2805, -3.3571) radius 0.5
  circle A577 centre (34.5732, -3.3571) radius 0.5
  circle A578 centre (37.8659, -3.3571) radius 0.5
  circle A579 centre (41.1585, -3.3571) radius 0.5
  circle A580 centre (44.4512, -3.3571) radius 0.5
  circle A581 centre (47.7439, -3.3571) radius 0.5
  circle A582 centre (51.0366, -3.3571) radius 0.5
  circle A583 centre (54.3293, -3.3571) radius 0.5
  circle A584 centre (57.622, -3.3571) radius 0.5
  circle A585 centre (60.9146, -3.3571) radius 0.5
  circle A586 centre (64.2073, -3.3571) radius 0.5
  circle A587 centre (67.5, -3.3571) radius 0.5
  circle A588 centre (-67.5, -0.5) radius 0.5
  circle A589 centre (-64.2073, -0.5) radius 0.5
  circle A590 centre (-60.9146, -0.5) radius 0.5
  circle A591 centre (-57.622, -0.5) radius 0.5
  circle A592 centre (-54.3293, -0.5) radius 0.5
  circle A593 centre (-51.0366, -0.5) radius 0.5
  circle A594 centre (-47.7439, -0.5) radius 0.5
  circle A595 centre (-44.4512, -0.5) radius 0.5
  circle A596 centre (-41.1585, -0.5) radius 0.5
  circle A597 centre (-37.8659, -0.5) radius 0.5
  circle A598 centre (-34.5732, -0.5) radius 0.5
  circle A599 centre (-31.2805, -0.5) radius 0.5
  circle A600 centre (-27.9878, -0.5) radius 0.5
  circle A601 centre (-24.6951, -0.5) radius 0.5
  circle A602 centre (-21.4024, -0.5) radius 0.5
  circle A603 centre (-18.1098, -0.5) radius 0.5
  circle A604 centre (-14.8171, -0.5) radius 0.5
  circle A605 centre (-11.5244, -0.5) radius 0.5
  circle A606 centre (-8.2317, -0.5) radius 0.5
  circle A607 centre (-4.939, -0.5) radius 0.5
  circle A608 centre (-1.6463, -0.5) radius 0.5
  circle A609 centre (1.6463, -0.5) radius 0.5
  circle A610 centre (4.939, -0.5) radius 0.5
  circle A611 centre (8.2317, -0.5) radius 0.5
  circle A612 centre (11.5244, -0.5) radius 0.5
  circle A613 centre (14.8171, -0.5) radius 0.5
  circle A614 centre (18.1098, -0.5) radius 0.5
  circle A615 centre (21.4024, -0.5) radius 0.5
  circle A616 centre (24.6951, -0.5) radius 0.5
  circle A617 centre (27.9878, -0.5) radius 0.5
  circle A618 centre (31.2805, -0.5) radius 0.5
  circle A619 centre (34.5732, -0.5) radius 0.5
  circle A620 centre (37.8659, -0.5) radius 0.5
  circle A621 centre (41.1585, -0.5) radius 0.5
  circle A622 centre (44.4512, -0.5) radius 0.5
  circle A623 centre (47.7439, -0.5) radius 0.5
  circle A624 centre (51.0366, -0.5) radius 0.5
  circle A625 centre (54.3293, -0.5) radius 0.5
  circle A626 centre (57.622, -0.5) radius 0.5
  circle A627 centre (60.9146, -0.5) radius 0.5
  circle A628 centre (64.2073, -0.5) radius 0.5
  circle A629 centre (67.5, -0.5) radius 0.5
  circle A630 centre (-67.5, 2.3571) radius 0.5
  circle A631 centre (-64.2073, 2.3571) radius 0.5
  circle A632 centre (-60.9146, 2.3571) radius 0.5
  circle A633 centre (-57.622, 2.3571) radius 0.5
  circle A634 centre (-54.3293, 2.3571) radius 0.5
  circle A635 centre (-51.0366, 2.3571) radius 0.5
  circle A636 centre (-47.7439, 2.3571) radius 0.5
  circle A637 centre (-44.4512, 2.3571) radius 0.5
  circle A638 centre (-41.1585, 2.3571) radius 0.5
  circle A639 centre (-37.8659, 2.3571) radius 0.5
  circle A640 centre (-34.5732, 2.3571) radius 0.5
  circle A641 centre (-31.2805, 2.3571) radius 0.5
  circle A642 centre (-27.9878, 2.3571) radius 0.5
  circle A643 centre (-24.6951, 2.3571) radius 0.5
  circle A644 centre (-21.4024, 2.3571) radius 0.5
  circle A645 centre (-18.1098, 2.3571) radius 0.5
  circle A646 centre (-14.8171, 2.3571) radius 0.5
  circle A647 centre (-11.5244, 2.3571) radius 0.5
  circle A648 centre (-8.2317, 2.3571) radius 0.5
  circle A649 centre (-4.939, 2.3571) radius 0.5
  circle A650 centre (-1.6463, 2.3571) radius 0.5
  circle A651 centre (1.6463, 2.3571) radius 0.5
  circle A652 centre (4.939, 2.3571) radius 0.5
  circle A653 centre (8.2317, 2.3571) radius 0.5
  circle A654 centre (11.5244, 2.3571) radius 0.5
  circle A655 centre (14.8171, 2.3571) radius 0.5
  circle A656 centre (18.1098, 2.3571) radius 0.5
  circle A657 centre (21.4024, 2.3571) radius 0.5
  circle A658 centre (24.6951, 2.3571) radius 0.5
  circle A659 centre (27.9878, 2.3571) radius 0.5
  circle A660 centre (31.2805, 2.3571) radius 0.5
  circle A661 centre (34.5732, 2.3571) radius 0.5
  circle A662 centre (37.8659, 2.3571) radius 0.5
  circle A663 centre (41.1585, 2.3571) radius 0.5
  circle A664 centre (44.4512, 2.3571) radius 0.5
  circle A665 centre (47.7439, 2.3571) radius 0.5
  circle A666 centre (51.0366, 2.3571) radius 0.5
  circle A667 centre (54.3293, 2.3571) radius 0.5
  circle A668 centre (57.622, 2.3571) radius 0.5
  circle A669 centre (60.9146, 2.3571) radius 0.5
  circle A670 centre (64.2073, 2.3571) radius 0.5
  circle A671 centre (67.5, 2.3571) radius 0.5
  circle A672 centre (-67.5, 5.2143) radius 0.5
  circle A673 centre (-64.2073, 5.2143) radius 0.5
  circle A674 centre (-60.9146, 5.2143) radius 0.5
  circle A675 centre (-57.622, 5.2143) radius 0.5
  circle A676 centre (-54.3293, 5.2143) radius 0.5
  circle A677 centre (-51.0366, 5.2143) radius 0.5
  circle A678 centre (-47.7439, 5.2143) radius 0.5
  circle A679 centre (-44.4512, 5.2143) radius 0.5
  circle A680 centre (-41.1585, 5.2143) radius 0.5
  circle A681 centre (-37.8659, 5.2143) radius 0.5
  circle A682 centre (-34.5732, 5.2143) radius 0.5
  circle A683 centre (-31.2805, 5.2143) radius 0.5
  circle A684 centre (-27.9878, 5.2143) radius 0.5
  circle A685 centre (-24.6951, 5.2143) radius 0.5
  circle A686 centre (-21.4024, 5.2143) radius 0.5
  circle A687 centre (-18.1098, 5.2143) radius 0.5
  circle A688 centre (-14.8171, 5.2143) radius 0.5
  circle A689 centre (-11.5244, 5.2143) radius 0.5
  circle A690 centre (-8.2317, 5.2143) radius 0.5
  circle A691 centre (-4.939, 5.2143) radius 0.5
  circle A692 centre (-1.6463, 5.2143) radius 0.5
  circle A693 centre (1.6463, 5.2143) radius 0.5
  circle A694 centre (4.939, 5.2143) radius 0.5
  circle A695 centre (8.2317, 5.2143) radius 0.5
  circle A696 centre (11.5244, 5.2143) radius 0.5
  circle A697 centre (14.8171, 5.2143) radius 0.5
  circle A698 centre (18.1098, 5.2143) radius 0.5
  circle A699 centre (21.4024, 5.2143) radius 0.5
  circle A700 centre (24.6951, 5.2143) radius 0.5
  circle A701 centre (27.9878, 5.2143) radius 0.5
  circle A702 centre (31.2805, 5.2143) radius 0.5
  circle A703 centre (34.5732, 5.2143) radius 0.5
  circle A704 centre (37.8659, 5.2143) radius 0.5
  circle A705 centre (41.1585, 5.2143) radius 0.5
  circle A706 centre (44.4512, 5.2143) radius 0.5
  circle A707 centre (47.7439, 5.2143) radius 0.5
  circle A708 centre (51.0366, 5.2143) radius 0.5
  circle A709 centre (54.3293, 5.2143) radius 0.5
  circle A710 centre (57.622, 5.2143) radius 0.5
  circle A711 centre (60.9146, 5.2143) radius 0.5
  circle A712 centre (64.2073, 5.2143) radius 0.5
  circle A713 centre (67.5, 5.2143) radius 0.5
  circle A714 centre (-67.5, 8.0714) radius 0.5
  circle A715 centre (-64.2073, 8.0714) radius 0.5
  circle A716 centre (-60.9146, 8.0714) radius 0.5
  circle A717 centre (-57.622, 8.0714) radius 0.5
  circle A718 centre (-54.3293, 8.0714) radius 0.5
  circle A719 centre (-51.0366, 8.0714) radius 0.5
  circle A720 centre (-47.7439, 8.0714) radius 0.5
  circle A721 centre (-44.4512, 8.0714) radius 0.5
  circle A722 centre (-41.1585, 8.0714) radius 0.5
  circle A723 centre (-37.8659, 8.0714) radius 0.5
  circle A724 centre (-34.5732, 8.0714) radius 0.5
  circle A725 centre (-31.2805, 8.0714) radius 0.5
  circle A726 centre (-27.9878, 8.0714) radius 0.5
  circle A727 centre (-24.6951, 8.0714) radius 0.5
  circle A728 centre (-21.4024, 8.0714) radius 0.5
  circle A729 centre (-18.1098, 8.0714) radius 0.5
  circle A730 centre (-14.8171, 8.0714) radius 0.5
  circle A731 centre (-11.5244, 8.0714) radius 0.5
  circle A732 centre (-8.2317, 8.0714) radius 0.5
  circle A733 centre (-4.939, 8.0714) radius 0.5
  circle A734 centre (-1.6463, 8.0714) radius 0.5
  circle A735 centre (1.6463, 8.0714) radius 0.5
  circle A736 centre (4.939, 8.0714) radius 0.5
  circle A737 centre (8.2317, 8.0714) radius 0.5
  circle A738 centre (11.5244, 8.0714) radius 0.5
  circle A739 centre (14.8171, 8.0714) radius 0.5
  circle A740 centre (18.1098, 8.0714) radius 0.5
  circle A741 centre (21.4024, 8.0714) radius 0.5
  circle A742 centre (24.6951, 8.0714) radius 0.5
  circle A743 centre (27.9878, 8.0714) radius 0.5
  circle A744 centre (31.2805, 8.0714) radius 0.5
  circle A745 centre (34.5732, 8.0714) radius 0.5
  circle A746 centre (37.8659, 8.0714) radius 0.5
  circle A747 centre (41.1585, 8.0714) radius 0.5
  circle A748 centre (44.4512, 8.0714) radius 0.5
  circle A749 centre (47.7439, 8.0714) radius 0.5
  circle A750 centre (51.0366, 8.0714) radius 0.5
  circle A751 centre (54.3293, 8.0714) radius 0.5
  circle A752 centre (57.622, 8.0714) radius 0.5
  circle A753 centre (60.9146, 8.0714) radius 0.5
  circle A754 centre (64.2073, 8.0714) radius 0.5
  circle A755 centre (67.5, 8.0714) radius 0.5